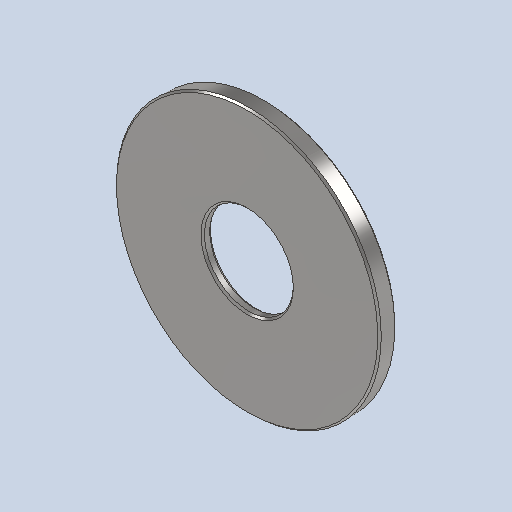
# Autodesk Inventor part: Einspannvorrichtung Beilagscheibe
Saved by Autodesk Inventor 2026.2 (Build 302298010, 298A)
## iProperties
Created: 2026-07-28
Part Number: Einspannvorrichtung Beilagscheibe
Material: Edelstahl
Document SubType Name: Modeling
Designer: moest
Density: 8 g/cm^3
Appearance: Halbpoliert
Author: moest
Autodesk Inventor part; units mm, degrees
ref_plane "YZ Plane" through (0, 0, 0) normal (1, 0, 0) x (0, 1, 0)
ref_plane "XZ Plane" through (0, 0, 0) normal (0, 1, 0) x (-1, 0, 0)
sketch "Skizze1" plane through (0, 0, 0) normal (0, 1, 0) x (-1, 0, 0)
  circle A0 centre (0, 0) radius 14.9
  dimension "d0" = 29.8
  constraints: 1 centre point, 1 coincident
  measures "d0" diameter of A0
extrude "Extrusion1" add sketch "Skizze1" along normal blind 2
chamfer "Fasen1" distance 0.1 distance2 2 1 edges at (14.9, 2, 0) measured on face at (1.7034, 2, 9.4126)
sketch "Skizze2" plane through (0, 2, 0) normal (0, 1, 0) x (1, 0, 0)
  circle A0 centre (0, 0) radius 8.5
  dimension "d6" = 17
  constraints: 1 centre point, 1 coincident
  measures "d6" diameter of A0
ref_plane "Arbeitsebene1" through (0, 1, 0) normal (0, 1, 0) x (1, 0, 0)
sketch "Skizze5" plane through (0, 2, 0) normal (0, 1, 0) x (1, 0, 0)
  circle A0 centre (0, 0) radius 5
  dimension "d17" = 10
  constraints: 1 centre point, 1 coincident
  measures "d17" diameter of A0
extrude "Extrusion2" cut sketch "Skizze5" against normal blind 2
chamfer "Fasen3" distance 3.5 distance2 1 1 edges at (-5, 2, 0) measured on face at (-11.3419, 2, -1.5795)
chamfer "Fasen4" distance 0.2 angle 45 5 edges at (-5, 0, 0) (-5, 1, 0) (14.9, 0.0005, 0) (14.9, 0, 0) (14.8005, 2, 0)
